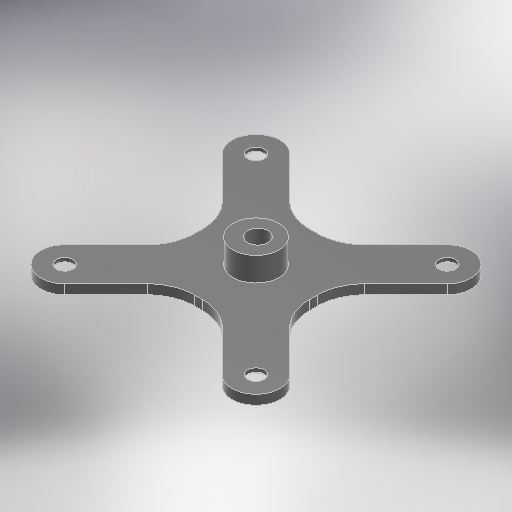
# Autodesk Inventor part: 3D_roter-encoder
Saved by Autodesk Inventor 2025.3 (Build 293356030, 356C)
## iProperties
Created: 2026-08-07
Part Number: 3D_roter-encoder
Material: 一般
Document SubType Name: Modeling
Designer: ibuki_ono
Density: 1 g/cm^3
Appearance: 滑らか - 黒
Author: ibuki_ono
## iProperties of the stored document 3D_roter-encoder_3D プリント.ipt
Created: 2026-09-06
Part Number: 3D_roter-encoder_3D プリント
Material: 一般
Document SubType Name: Modeling
Designer: ibuki_ono
Density: 1 g/cm^3
Appearance: 既定
Author: ibuki_ono
Autodesk Inventor part; units mm, degrees
ref_plane "YZ Plane" through (0, 0, 0) normal (1, 0, 0) x (0, 1, 0)
ref_plane "XZ Plane" through (0, 0, 0) normal (0, 1, 0) x (-1, 0, 0)
ref_plane "XY Plane" through (0, 0, 0) normal (0, 0, 1) x (1, 0, 0)
sketch "スケッチ1" plane through (0, 0, 0) normal (0, 1, 0) x (-1, 0, 0)
  line L0 (-20, 20) -> (20, -20) construction
  line L1 (-23.5355, 16.4645) -> (16.4645, -23.5355)
  line L2 (23.5355, -16.4645) -> (-16.4645, 23.5355)
  arc A0 (-16.4645, 23.5355) -> (-23.5355, 16.4645) centre (-20, 20) ccw
  arc A1 (16.4645, -23.5355) -> (23.5355, -16.4645) centre (20, -20) ccw
  line L3 (0, 0) -> (56.5685, 0) construction
  line L4 (-20, -20) -> (20, 20) construction
  line L5 (-16.4645, -23.5355) -> (23.5355, 16.4645)
  line L6 (16.4645, 23.5355) -> (-23.5355, -16.4645)
  arc A2 (-23.5355, -16.4645) -> (-16.4645, -23.5355) centre (-20, -20) ccw
  arc A3 (23.5355, 16.4645) -> (16.4645, 23.5355) centre (20, 20) ccw
  line L7 (0, 0) -> (56.5685, 0) construction
  line L8 (-12, 12) -> (12, 12)
  line L9 (12, 12) -> (12, -12)
  line L10 (12, -12) -> (-12, -12)
  line L11 (-12, -12) -> (-12, 12)
  line L12 (-12, 12) -> (12, -12) construction
  line L13 (12, 12) -> (-12, -12) construction
  point P0 (12, 4.9289)
  point P1 (4.9289, 12)
  point P2 (-4.9289, 12)
  point P3 (-12, 4.9289)
  point P4 (-12, -4.9289)
  point P5 (-4.9289, -12)
  point P6 (4.9289, -12)
  point P7 (12, -4.9289)
  dimension "d0" = 45
  dimension "d1" = 10
  dimension "d3" = 45
  dimension "d4" = 10
  dimension "d5" = 40
  dimension "d6" = 24
  dimension "d7" = 24
  constraints: 32 end point, 8 point on circle, 8 tangent, 4 centre point, 4 midpoint, 4 parallel, 3 horizontal, 2 equal length, 2 perpendicular, 1 horizontal alignment
  measures "d0" angle of L0 L3
  measures "d1" diameter of A1
  measures "d3" angle of L7 L4
  measures "d4" diameter of A3
  measures "d5" distance of L4.start L0.end
  measures "d6" distance of L9.end L10.end
  measures "d7" distance of L8.end L9.end
extrude "押し出し1" add sketch "スケッチ1" along normal blind 2
sketch "スケッチ2" plane through (0, 2, 0) normal (0, 1, 0) x (1, 0, 0)
  circle A0 centre (0, 0) radius 4.8
  dimension "d10" = 9.6
  constraints: 1 centre point, 1 coincident
  measures "d10" diameter of A0
extrude "押し出し2" add sketch "スケッチ2" along normal blind 5
sketch "スケッチ4" plane through (0, 0, 0) normal (0, -1, 0) x (1, 0, 0)
  arc A0 (23.5355, 16.4645) -> (16.4645, 23.5355) centre (20, 20) ccw projected
  arc A1 (16.4645, -23.5355) -> (23.5355, -16.4645) centre (20, -20) ccw projected
  arc A2 (-23.5355, -16.4645) -> (-16.4645, -23.5355) centre (-20, -20) ccw projected
  arc A3 (-16.4645, 23.5355) -> (-23.5355, 16.4645) centre (-20, 20) ccw projected
  point P0 (0, 0)
hole "穴2" at (-20, 0, 20) at (20, 0, 20) at (20, 0, -20) at (-20, 0, -20) direction (0, 1, 0) diameter 3.5 end through all counterbore diameter 7 counterbore depth 1
sketch "スケッチ5" plane through (20, 1, 20) normal (0, -1, 0) x (1, 0, 0)
  circle A0 centre (0, 0) radius 3.5 projected
  circle A1 centre (0, 0) radius 1.75 projected
  line L0 (1.75, 3.0311) -> (1.75, -3.0311)
  line L1 (1.75, 3.0311) -> (7.8122, 3.0311) construction
  line L2 (1.75, -3.0311) -> (-3.5, 0)
  line L3 (1.75, -3.0311) -> (7.8122, -3.0311) construction
  circle A2 centre (0, 0) radius 3.5 projected
  line L4 (-3.5, 0) -> (1.75, 3.0311)
  line L5 (-3.5, 0) -> (2.5622, 0) construction
  circle A3 centre (0, 0) radius 1.75 projected
  point P0 (-20, -20)
  point P1 (-0.875, 1.5155)
  point P2 (-3.5, 0)
  point P3 (-0.875, -1.5155)
  point P4 (1.75, 3.0311)
  point P5 (1.75, 0)
  point P6 (1.75, -3.0311)
  dimension "d27" = 90
  dimension "d28" = 150
  dimension "d29" = 30
  constraints: 12 end point, 6 point on circle, 3 equal length, 3 horizontal, 3 tangent
  measures "d27" angle of L0 L1
  measures "d28" angle of L3 L2
  measures "d29" angle of L5 L4
extrude "押し出し3" cut sketch "スケッチ5" against normal blind 0.2 contours L0 A1 L4 | L2 A1 L0 | L4 A1 L2
mirror "ミラー1" about plane through (0, 0, 0) normal (1, 0, 0) of "押し出し3"
mirror "ミラー2" about plane through (0, 0, 0) normal (0, 0, 1) of "押し出し3", "ミラー1"
sketch "スケッチ6" plane through (0, 0, 0) normal (0, -1, 0) x (1, 0, 0)
  circle A0 centre (0.2, -0.2) radius 3.05
  point P0 (0, 0)
  dimension "d42" = 6.1
  dimension "d43" = 0.2
  dimension "d44" = 0.2
  constraints: 1 centre point
  measures "d42" diameter of A0
  measures "d43" horizontal distance of point (0, 0) A0.centre
  measures "d44" horizontal distance of point (0, 0) A0.centre
extrude "押し出し4" cut sketch "スケッチ6" against normal blind 2.2
sketch "スケッチ7" plane through (0, 7, 0) normal (0, 1, 0) x (1, 0, 0)
  circle A0 centre (0.2, 0.2) radius 3.05 projected
  circle A1 centre (0.2, 0.2) radius 2.15
  point P0 (0, 0)
  dimension "d45" = 4.3
  constraints: 1 centre point, 1 coincident
  measures "d45" diameter of A1
extrude "押し出し5" cut sketch "スケッチ7" against normal through all contours A1
fillet "フィレット1" radius 10 8 edges at (-12, 1, 4.9289) (-12, 1, -4.9289) (-4.9289, 1, 12) (4.9289, 1, 12) (12, 1, 4.9289) (12, 1, -4.9289) (4.9289, 1, -12) (-4.9289, 1, -12)
chamfer "面取り1" distance 0.4 angle 45 1 edges at (-2.85, 0, -0.2)
sketch "スケッチ8" plane through (0, 0, 0) normal (0, -1, 0) x (1, 0, 0)
  line L0 (5.2721, -3.2132) -> (3.2132, -5.2721)
  line L1 (3.2132, -5.2721) -> (7.0711, -7.0711)
  line L2 (7.0711, -7.0711) -> (5.2721, -3.2132)
  line L3 (0, 0) -> (7.0711, -7.0711) construction
  line L4 (0, 0) -> (10, 0) construction
  point P0 (4.2426, -4.2426)
  dimension "d46" = 10
  dimension "d47" = 45
  dimension "d48" = 70
  dimension "d49" = 4
  constraints: 10 end point, 1 equal length, 1 horizontal, 1 midpoint, 1 perpendicular, 1 point on line
  measures "d46" distance of L1.end L3.start
  measures "d47" angle of L3 L4
  measures "d48" angle of L0 L2
  measures "d49" distance from line of L1.end L0
extrude "押し出し6" cut sketch "スケッチ8" against normal blind 0.4
equation "\"d7\" = d6"
equation "\"d44\" = d43"
